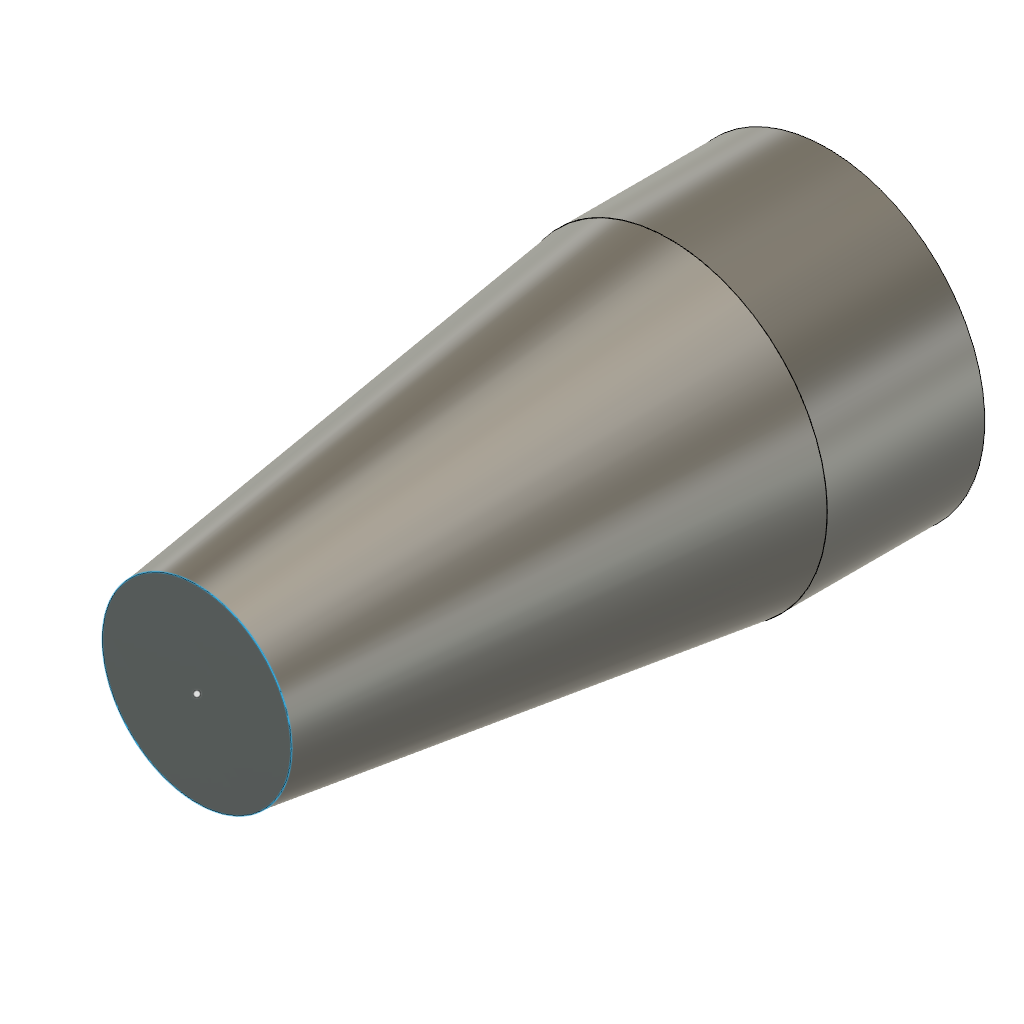
face_free (Autodesk Fusion 360 design; units mm, degrees)
part number: 2026-10-20-22-41-14-999
Autodesk Fusion 360 part; units mm, degrees
sketch "LoftFaceSeedSection" plane through (0, 0, 0) normal (0, 0, 1) x (1, 0, 0)
  circle A0 centre (0, 0) radius 10
extrude "LoftFaceCylinderSeed" add sketch "LoftFaceSeedSection" along normal blind 10 makes body 1
ref_plane "WorkPlane1" through (0, 0, 40) normal (0, 0, 1) x (1, 0, 0)
sketch "LoftFaceDestinationSection" plane through (0, 0, 40) normal (0, 0, 1) x (1, 0, 0)
  circle A0 centre (0, 0) radius 6
loft "ProbeLoftFace" add profiles "LoftFaceDestinationSection" section 1 face at (2.3712, -3.5556, 10) section 2 separate body on bodies 1 makes body 2
named bodies: "LoftFaceCylinderBody"
